TESTWATERPROOF (Autodesk Fusion 360 design; units mm, degrees)
Autodesk Fusion 360 part; units mm, degrees
sketch "Sketch1" plane through (0, 0, 0) normal (0, 1, 0) x (1, 0, 0)
  line L0 (21.7, -14.425) -> (-21.7, -14.425)
  line L1 (-21.7, -14.425) -> (-21.7, 14.425)
  line L2 (-21.7, 14.425) -> (21.7, 14.425)
  line L3 (21.7, 14.425) -> (21.7, -14.425)
  line L4 (21.7, -14.425) -> (-21.7, 14.425) construction
  line L5 (-21.7, -14.425) -> (21.7, 14.425) construction
  line L6 (10.500962, -10.425) -> (-10.500962, -10.425)
  line L7 (-10.500962, -10.425) -> (-10.500962, 10.425)
  line L8 (-10.500962, 10.425) -> (10.500962, 10.425)
  line L9 (10.500962, 10.425) -> (10.500962, -10.425)
  line L10 (10.500962, -10.425) -> (-10.500962, 10.425) construction
  line L11 (-10.500962, -10.425) -> (10.500962, 10.425) construction
  line L12 (0, -14.425) -> (0, -12.925)
  line L13 (-21.7, 0) -> (-20.7, 0)
  line L14 (0, 14.425) -> (0, 12.925)
  dimension "d1" = 28.85
  dimension "d2" = 43.4
  dimension "d3" = 20.85
  dimension "d4" = 1.5
  dimension "d5" = 1
  dimension "d6" = 1.5
  constraint perpendicular L0 L1
  constraint parallel L0 L2
  constraint parallel L1 L3
  constraint horizontal L0
  constraint coincident L4 origin
  constraint coincident L5 origin
  constraint perpendicular L6 L7
  constraint parallel L6 L8
  constraint parallel L7 L9
  constraint horizontal L6
  constraint coincident L10 origin
  constraint coincident L11 origin
  constraint midpoint L0 L12.start
  constraint midpoint L1 L13.start
  constraint midpoint L2 L14.start
  measures "d1" distance of L0.end L1.end
  measures "d2" distance of L1.end L2.end
  measures "d4" distance of L12.start L12.end
  measures "d5" distance of L13.start L13.end L1
  measures "d6" distance of L14.start L14.end
extrude "Extrude1" add sketch "Sketch1" along normal blind 3 contours L0 L1 L2 L3 | L6 L7 L8 L9 picked at (17.966987, -3.475) picked at (-3.500321, -3.475) makes body 1
sketch "Sketch2" plane through (0, 3, 0) normal (0, 1, 0) x (-1, 0, 0)
  line L0 (-21.7, -14.425) -> (21.7, -14.425)
  line L1 (21.7, -14.425) -> (21.7, 14.425)
  line L2 (21.7, 14.425) -> (-21.7, 14.425)
  line L3 (-21.7, 14.425) -> (-21.7, -14.425)
  line L4 (-10, 10) -> (10, 10)
  line L5 (10, 10) -> (10, -10)
  line L6 (10, -10) -> (-10, -10)
  line L7 (-10, -10) -> (-10, 10)
  line L8 (-10, 10) -> (10, -10) construction
  line L9 (10, 10) -> (-10, -10) construction
  dimension "d9" = 20
  dimension "d10" = 20
  constraint perpendicular L4 L5
  constraint parallel L4 L6
  constraint parallel L5 L7
  constraint horizontal L4
  constraint coincident L8 origin
  constraint coincident L9 origin
  measures "d9" distance of L5.end L6.end
  measures "d10" distance of L4.end L5.end
extrude "Extrude2" add sketch "Sketch2" along normal blind 20 contours L0 L1 L2 L3 picked at (17.8, 3.333333) bodies 1
sketch "Sketch3" plane through (0, 23, 0) normal (0, 1, 0) x (-1, 0, 0)
  line L0 (10, -10) -> (-10, -10)
  line L1 (-10, -10) -> (-10, 10)
  line L2 (-10, 10) -> (10, 10)
  line L3 (10, 10) -> (10, -10)
  line L4 (-21.7, 14.425) -> (-21.7, -14.425)
  line L5 (-21.7, -14.425) -> (21.7, -14.425)
  line L6 (21.7, -14.425) -> (21.7, 14.425)
  line L7 (21.7, 14.425) -> (-21.7, 14.425)
  line L8 (21.7, 0) -> (20.2, 0)
  line L9 (-20.2, 12.675) -> (20.2, 12.675)
  line L10 (20.2, 12.675) -> (20.2, -12.675)
  line L11 (20.2, -12.675) -> (-20.2, -12.675)
  line L12 (-20.2, -12.675) -> (-20.2, 12.675)
  line L13 (-20.2, 12.675) -> (20.2, -12.675) construction
  line L14 (20.2, 12.675) -> (-20.2, -12.675) construction
  line L15 (-19.2, 11.675) -> (19.2, 11.675)
  line L16 (19.2, 11.675) -> (19.2, -11.675)
  line L17 (19.2, -11.675) -> (-19.2, -11.675)
  line L18 (-19.2, -11.675) -> (-19.2, 11.675)
  line L19 (-19.2, 11.675) -> (19.2, -11.675) construction
  line L20 (19.2, 11.675) -> (-19.2, -11.675) construction
  dimension "d17" = 40.4
  dimension "d18" = 25.35
  dimension "d19" = 38.4
  dimension "d20" = 23.35
  constraint midpoint L6 L8.start
  constraint perpendicular L9 L10
  constraint parallel L9 L11
  constraint parallel L10 L12
  constraint horizontal L9
  constraint coincident L13 origin
  constraint coincident L14 origin
  constraint perpendicular L15 L16
  constraint parallel L15 L17
  constraint parallel L16 L18
  constraint horizontal L15
  constraint coincident L19 origin
  constraint coincident L20 origin
  measures "d17" distance of L10.end L11.end
  measures "d18" distance of L9.end L10.end
  measures "d19" distance of L16.end L17.end
  measures "d20" distance of L15.end L16.end
extrude "Extrude3" cut sketch "Sketch3" against normal blind 1 contours L9 L10 L11 L12 picked at (19.533333, 0) bodies 1
fillet "Fillet1" radius 2.5 8 edges at (-20.2, 22.5, -12.675) (-19.2, 22.5, -11.675) (19.2, 22.5, -11.675) (20.2, 22.5, -12.675) (19.2, 22.5, 11.675) (20.2, 22.5, 12.675) (-19.2, 22.5, 11.675) (-20.2, 22.5, 12.675) on bodies 1
sketch "Sketch4" plane through (0, 23, 0) normal (0, 1, 0) x (-1, 0, 0)
  arc A0 (19.2, 9.175) -> (16.7, 11.675) centre (16.7, 9.175) ccw
  line L0 (16.7, 11.675) -> (-16.7, 11.675)
  arc A1 (-16.7, 11.675) -> (-19.2, 9.175) centre (-16.7, 9.175) ccw
  line L1 (-19.2, 9.175) -> (-19.2, -9.175)
  arc A2 (-19.2, -9.175) -> (-16.7, -11.675) centre (-16.7, -9.175) ccw
  line L2 (-16.7, -11.675) -> (16.7, -11.675)
  arc A3 (16.7, -11.675) -> (19.2, -9.175) centre (16.7, -9.175) ccw
  line L3 (19.2, -9.175) -> (19.2, 9.175)
  line L4 (10, -10) -> (-10, -10)
  line L5 (-10, -10) -> (-10, 10)
  line L6 (-10, 10) -> (10, 10)
  line L7 (10, 10) -> (10, -10)
  line L8 (21.7, -14.425) -> (21.7, 14.425)
  line L9 (21.7, 0) -> (14.7, 0)
  line L10 (-21.7, 14.425) -> (-21.7, -14.425)
  line L11 (-21.7, 0) -> (-14.7, 0)
  circle A4 centre (14.7, 0) radius 1.25
  circle A5 centre (-14.7, 0) radius 1.25
  dimension "d24" = 7
  dimension "d25" = 7
  dimension "d26" = 2.5
  dimension "d27" = 2.5
  constraint midpoint L8 L9.start
  constraint midpoint L10 L11.start
  constraint coincident L9.end A4.centre
  constraint coincident L11.end A5.centre
  measures "d24" distance of L9.start L9.end
  measures "d25" distance of L11.start L11.end
  measures "d26" diameter of A4
  measures "d27" diameter of A5
extrude "Extrude4" cut sketch "Sketch4" against normal blind 10 contours A4 | A5 picked at (15.046701, -0.563792) picked at (-14.852225, -0.387864) bodies 1
thread "Thread1" "ISO Metric profile 2.5 M2.5x0.45 6H" major diameter 2.58 minor diameter 2.0755 pitch 0.45 angle 60 modelled right hand crest width 0.05625 on face at (-15.948446, 16.333333, -0.062307) crest through (-15.73775, 23.253125, 0) on bodies 1
thread "Thread2" "ISO Metric profile 2.5 M2.5x0.45 6H" major diameter 2.58 minor diameter 2.0755 pitch 0.45 angle 60 modelled right hand crest width 0.05625 on face at (13.451554, 16.333333, -0.062307) crest through (13.66225, 23.253125, 0) on bodies 1
sketch "Sketch5" plane through (0, 0, 0) normal (0, 0, 1) x (1, 0, 0)
sketch "Sketch6" plane through (0, 0, 0) normal (0, 1, 0) x (1, 0, 0)
  line L0 (21.7, -14.425) -> (-21.7, -14.425)
  line L1 (-21.7, -14.425) -> (-21.7, 14.425)
  line L2 (21.7, -54.425001) -> (-21.7, -54.425001)
  line L3 (-21.7, -54.425001) -> (-21.7, -25.575001)
  line L4 (-21.7, -25.575001) -> (21.7, -25.575001)
  line L5 (21.7, -25.575001) -> (21.7, -54.425001)
  line L6 (21.7, -54.425001) -> (-21.7, -25.575001) construction
  line L7 (-21.7, -54.425001) -> (21.7, -25.575001) construction
  point P0 (0, -40.000001)
  dimension "d30" = 43.4
  dimension "d31" = 28.85
  dimension "d32" = 43.4
  dimension "d33" = 28.85
  constraint perpendicular L2 L3
  constraint parallel L2 L4
  constraint parallel L3 L5
  constraint horizontal L2
  measures "d30" horizontal distance of L0.start L0.end
  measures "d31" vertical distance of L0.end L1.end
extrude "Extrude5" add sketch "Sketch6" along normal blind 3 separate body contours L2 L3 L4 L5 picked at (-7.233333, -35.191667) makes body 2
sketch "Sketch7" plane through (0, 3, 0) normal (0, 1, 0) x (-1, 0, 0)
  line L0 (-21.7, 25.575001) -> (21.7, 25.575001)
  line L1 (21.7, 25.575001) -> (21.7, 54.425001)
  line L2 (21.7, 54.425001) -> (-21.7, 54.425001)
  line L3 (-21.7, 54.425001) -> (-21.7, 25.575001)
  line L4 (21.7, 40.000001) -> (14.7, 40.000001)
  line L5 (-21.7, 40.000001) -> (-14.7, 40.000001)
  circle A0 centre (14.7, 40.000001) radius 1.375
  circle A1 centre (-14.7, 40.000001) radius 1.375
  dimension "d36" = 7
  dimension "d37" = 7
  dimension "d38" = 2.75
  dimension "d39" = 2.75
  measures "d38" diameter of A0
  measures "d39" diameter of A1
extrude "Extrude6" cut sketch "Sketch7" against normal up to surface (3 mm away) contours A0 | A1 picked at (14.252805, 39.741812) picked at (-14.801989, 40.446843) bodies 2
sketch "Sketch8" plane through (0, 3, 0) normal (0, 1, 0) x (-1, 0, 0)
  circle A0 centre (14.7, 40.000001) radius 1.375
  circle A1 centre (-14.7, 40.000001) radius 1.375
  line L0 (-21.7, 25.575001) -> (21.7, 25.575001)
  line L1 (21.7, 25.575001) -> (21.7, 54.425001)
  line L2 (21.7, 54.425001) -> (-21.7, 54.425001)
  line L3 (-21.7, 54.425001) -> (-21.7, 25.575001)
  line L4 (-20.2, 52.675001) -> (20.2, 52.675001)
  line L5 (20.2, 52.675001) -> (20.2, 27.325001)
  line L6 (20.2, 27.325001) -> (-20.2, 27.325001)
  line L7 (-20.2, 27.325001) -> (-20.2, 52.675001)
  line L8 (-20.2, 52.675001) -> (20.2, 27.325001) construction
  line L9 (20.2, 52.675001) -> (-20.2, 27.325001) construction
  line L10 (-19.2, 51.675001) -> (19.2, 51.675001)
  line L11 (19.2, 51.675001) -> (19.2, 28.325001)
  line L12 (19.2, 28.325001) -> (-19.2, 28.325001)
  line L13 (-19.2, 28.325001) -> (-19.2, 51.675001)
  line L14 (-19.2, 51.675001) -> (19.2, 28.325001) construction
  line L15 (19.2, 51.675001) -> (-19.2, 28.325001) construction
  point P0 (0, 40.000001)
  point P1 (0, 40.000001)
  dimension "d42" = 40.4
  dimension "d43" = 25.35
  dimension "d44" = 38.4
  dimension "d45" = 23.35
  constraint perpendicular L4 L5
  constraint parallel L4 L6
  constraint parallel L5 L7
  constraint horizontal L4
  constraint perpendicular L10 L11
  constraint parallel L10 L12
  constraint parallel L11 L13
  constraint horizontal L10
extrude "Extrude7" cut sketch "Sketch8" against normal blind 1 contours L4 L5 L6 L7 picked at (6.4, 27.658334) bodies 2
sketch "Sketch9" plane through (0, 3, 0) normal (0, 1, 0) x (-1, 0, 0)
  line L0 (-19.2, 51.675001) -> (-19.2, 28.325001)
  line L1 (-19.2, 28.325001) -> (19.2, 28.325001)
  line L2 (19.2, 28.325001) -> (19.2, 51.675001)
  line L3 (19.2, 51.675001) -> (-19.2, 51.675001)
  circle A0 centre (14.7, 40.000001) radius 1.375
  circle A1 centre (-14.7, 40.000001) radius 1.375
  line L4 (-10, 50.000001) -> (10, 50.000001)
  line L5 (10, 50.000001) -> (10, 30.000001)
  line L6 (10, 30.000001) -> (-10, 30.000001)
  line L7 (-10, 30.000001) -> (-10, 50.000001)
  line L8 (-10, 50.000001) -> (10, 30.000001) construction
  line L9 (10, 50.000001) -> (-10, 30.000001) construction
  point P0 (0, 40.000001)
  dimension "d48" = 20
  dimension "d49" = 20
  constraint perpendicular L4 L5
  constraint parallel L4 L6
  constraint parallel L5 L7
  constraint horizontal L4
extrude "Extrude8" cut sketch "Sketch9" against normal blind 1 contours L4 L5 L6 L7 picked at (-3.333333, 43.333334) bodies 2
fillet "Fillet2" radius 2.5 8 edges at (-19.2, 2.5, 28.325001) (-20.2, 2.5, 27.325001) (-19.2, 2.5, 51.675001) (-20.2, 2.5, 52.675001) (19.2, 2.5, 51.675001) (20.2, 2.5, 52.675001) (20.2, 2.5, 27.325001) (19.2, 2.5, 28.325001) on bodies 2
